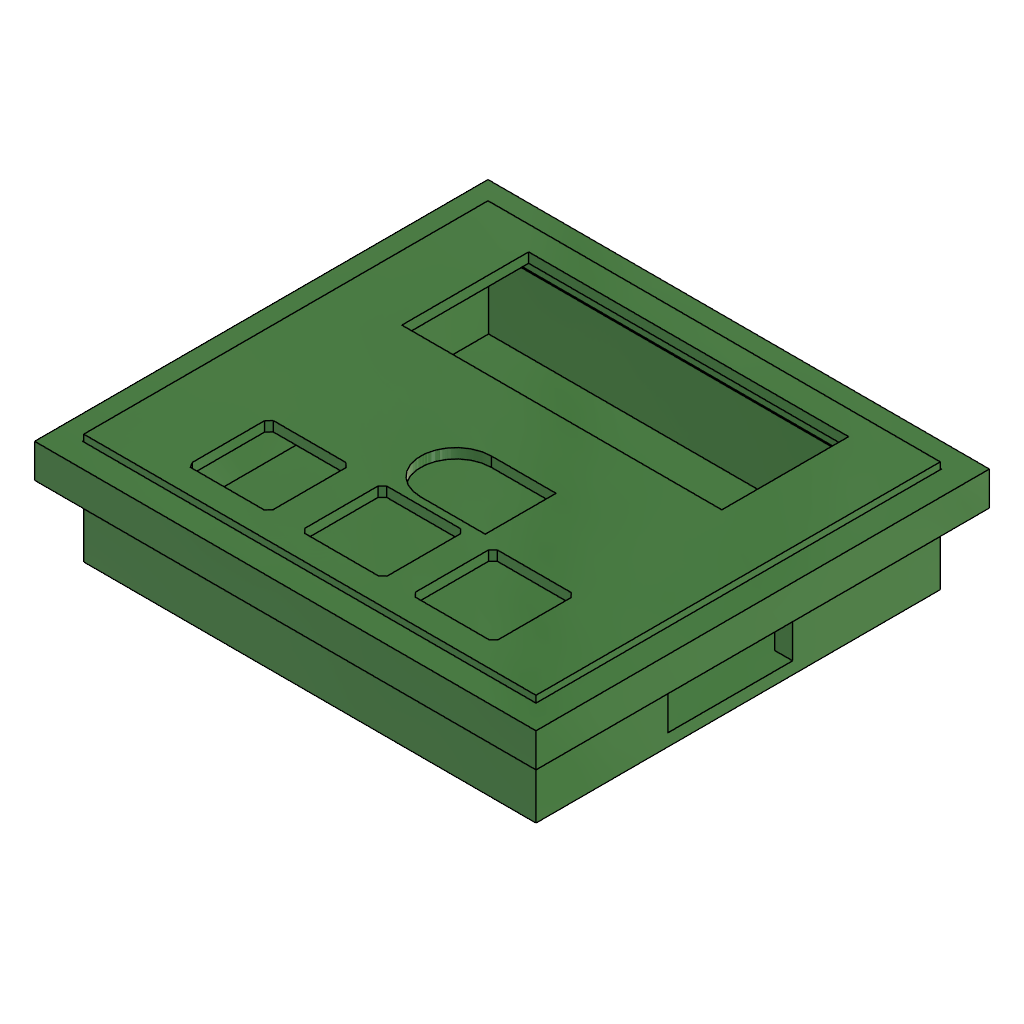
Rhino Motion RMCS-610 digital speed controller (Autodesk Fusion 360 design; units mm, degrees)
part number: 2026-09-15-11-50-59-737
Autodesk Fusion 360 part; units mm, degrees
sketch "Sketch1" plane through (0, 0, 0) normal (0, 0, 1) x (1, 0, 0)
  line L0 (0, 0) -> (67.5, 0)
  line L1 (67.5, 0) -> (67.5, 59.7)
  line L2 (67.5, 59.7) -> (0, 59.7)
  line L3 (0, 59.7) -> (0, 0)
  line L4 (8, 58.3) -> (59, 58.3)
  line L5 (59, 58.3) -> (59, 38.7)
  line L6 (59, 38.7) -> (8, 38.7)
  line L7 (8, 38.7) -> (8, 58.3)
  circle A0 centre (33.2, 21.3) radius 5.75
  line L8 (28.2142, 1.7129) -> (28.2142, 13.6129)
  line L9 (28.2142, 13.6129) -> (28.9271, 14.3142)
  line L10 (40.9271, 14.3142) -> (41.6283, 13.6012)
  line L11 (40.9154, 1) -> (28.9154, 1)
  line L12 (28.9154, 1) -> (28.2142, 1.7129)
  line L13 (41.6283, 1.7012) -> (40.9154, 1)
  line L14 (28.9271, 14.3142) -> (40.9271, 14.3142)
  line L15 (41.6283, 13.6012) -> (41.6283, 1.7012)
  line L16 (46.1883, 1.7129) -> (46.1883, 13.6129)
  line L17 (46.1883, 13.6129) -> (46.9013, 14.3142)
  line L18 (58.9013, 14.3142) -> (59.6025, 13.6012)
  line L19 (58.8895, 1) -> (46.8895, 1)
  line L20 (46.8895, 1) -> (46.1883, 1.7129)
  line L21 (59.6025, 1.7012) -> (58.8895, 1)
  line L22 (46.9013, 14.3142) -> (58.9013, 14.3142)
  line L23 (59.6025, 13.6012) -> (59.6025, 1.7012)
  circle A1 centre (34.453, 7.8982) radius 3.315
  circle A2 centre (52.6325, 7.8982) radius 3.315
  line L24 (22.3245, 1) -> (10.3245, 1)
  line L25 (22.29, 14.3138) -> (23.0142, 13.6241)
  circle A3 centre (16.2543, 7.8982) radius 3.315
  line L26 (9.8, 13.5897) -> (10.4897, 14.3138)
  line L27 (23.0142, 1.7241) -> (22.3245, 1)
  line L28 (10.3245, 1) -> (9.8, 1.8514)
  line L29 (23.0142, 13.6241) -> (23.0142, 1.7241)
  line L30 (9.8, 1.8514) -> (9.8, 13.5897)
  line L31 (10.4897, 14.3138) -> (22.29, 14.3138)
  line L32 (33.2, 27.05) -> (43.7, 27.05)
  line L33 (43.7, 27.05) -> (43.7, 15.55)
  line L34 (33.2, 27.05) -> (33.2, 15.55)
  line L35 (33.2, 15.55) -> (43.7, 15.55)
  dimension "d1" = 59.7
  dimension "d2" = 67.5
  dimension "d11" = 51
  dimension "d12" = 19.6
  dimension "d13" = 1.4
  dimension "d15" = 11.5
  dimension "d29" = 1
  dimension "d30" = 1
  dimension "d31" = 1
  dimension "d32" = 1
  dimension "d34" = 12
  dimension "d36" = 11.9
  dimension "d37" = 1
  dimension "d38" = 1
  dimension "d39" = 1
  dimension "d40" = 1
  dimension "d41" = 12
  dimension "d44" = 11.9
  dimension "d46" = 4.56
  dimension "d50" = 1
  dimension "d51" = 1
  dimension "d61" = 6.63
  dimension "d62" = 6.63
  dimension "d68" = 1
  dimension "d69" = 1
  dimension "d70" = 1
  dimension "d71" = 1
  dimension "d73" = 12
  dimension "d75" = 11.9
  dimension "d76" = 6.63
  dimension "d79" = 5.2
  dimension "d80" = 1
  dimension "d83" = 9.8
  dimension "d84" = 8
  dimension "d336" = 10.5
  dimension "d337" = 11.65
  dimension "d338" = 23.8
  constraint horizontal L0
  constraint vertical L1
  constraint horizontal L2
  constraint vertical L3
  constraint coincident L0.start L3.end
  constraint horizontal L4
  constraint vertical L5
  constraint horizontal L6
  constraint vertical L7
  constraint perpendicular L9 L10
  constraint perpendicular L14 L15
  constraint perpendicular L10 L13
  constraint perpendicular L11 L15
  constraint perpendicular L17 L18
  constraint perpendicular L22 L23
  constraint perpendicular L18 L21
  constraint perpendicular L19 L23
  constraint perpendicular L25 L26
  constraint perpendicular L29 L31
  constraint perpendicular L25 L27
  constraint perpendicular L24 L29
  constraint coincident A0 L32.start
  constraint tangent A0 L32
  constraint horizontal L32
  constraint perpendicular L32 L33
  constraint coincident A0 L34.end
  constraint perpendicular A0 L34
  constraint horizontal L35
  constraint horizontal A1.centre A2.centre
  constraint horizontal A1.centre A3.centre
  measures "d1" distance of L0.end L1.end
  measures "d2" distance of L1.end L2.end
  measures "d11" distance of L5.end L6.end
  measures "d12" distance of L4.end L5.end
  measures "d13" distance of L2 L4
  measures "d15" diameter of A0
  measures "d29" distance of L8.end L9.end
  measures "d30" distance of L10.start L10.end
  measures "d31" distance of L8.start L11.end
  measures "d32" distance of L13.start L11.start
  measures "d34" distance of L11.end L11.start
  measures "d36" distance of L13.start L10.end
  measures "d37" distance of L16.end L17.end
  measures "d38" distance of L18.start L18.end
  measures "d39" distance of L16.start L19.end
  measures "d40" distance of L21.start L19.start
  measures "d41" distance of L17.end L18.start
  measures "d44" distance of L21.start L18.end
  measures "d46" distance of L15 L16
  measures "d50" distance of L0 L11
  measures "d51" distance of L0 L19
  measures "d61" diameter of A1
  measures "d62" diameter of A2
  measures "d68" distance of L26.start L26.end
  measures "d69" distance of L25.end L25.start
  measures "d70" distance of L28.end L24.end
  measures "d71" distance of L27.start L24.start
  measures "d73" distance of L24.end L24.start
  measures "d75" distance of L25.end L27.start
  measures "d76" diameter of A3
  measures "d79" distance of L8 L29
  measures "d80" distance of L0 L24
  measures "d83" distance of L3 L30
  measures "d84" distance of L3 L7
  measures "d336" distance of L32.start L32.end
  measures "d337" distance of L6 L32
  measures "d338" distance of L1 L33
sketch "Sketch2" plane through (0, 0, 0) normal (0, 0, 1) x (1, 0, 0)
  line L0 (55.5, 18.44) -> (63.5, 18.44)
  line L1 (63.5, 18.44) -> (63.5, 38.7)
  line L2 (63.5, 38.7) -> (55.5, 38.7)
  line L3 (55.5, 38.7) -> (55.5, 18.44)
  line L4 (67.5, 59.7) -> (0, 59.7)
  line L5 (67.5, 0) -> (67.5, 59.7)
  dimension "d86" = 20.26
  dimension "d87" = 8
  dimension "d88" = 21
  dimension "d89" = 4
  constraint horizontal L0
  constraint vertical L1
  constraint horizontal L2
  constraint vertical L3
  measures "d86" distance of L0.end L1.end
  measures "d87" distance of L0.start L0.end
  measures "d88" distance of L2 L4
  measures "d89" distance of L1 L5
extrude "Extrude99" add sketch "Sketch1" along normal blind 1.6 contours L0 L1 L2 L3 makes body 1
extrude "Extrude100" add sketch "Sketch2" against normal blind 10.4 bodies 1
extrude "Extrude101" add sketch "Sketch1" along normal blind 1 contours A0 L32 L33 L35 | L8 L9 L10 L11 L12 L13 L14 L15 | L16 L17 L18 L19 L20 L21 L22 L23 | L24 L25 L26 L27 L28 L29 L30 L31 bodies 1
extrude "Extrude102" add sketch "Sketch1" along normal blind 2 contours A0 L34 | A0 L34 | A1 | A2 | A3 bodies 1
extrude "Extrude103" add 1 faces at (35.7318, 22.5192, 2) along direction (0, 0, 1) blind 2 on bodies 1 bodies 1
ref_plane "WorkPlane12" through (33.75, 29.85, 1.6) normal (0, 0, 1) x (1, 0, 0)
sketch "Sketch18" plane through (0, 0, 1.6) normal (0, 0, 1) x (1, 0, 0)
  line L0 (0, 59.7) -> (0, 0)
  line L1 (0, 0) -> (67.5, 0)
  line L2 (67.5, 0) -> (67.5, 59.7)
  line L3 (67.5, 59.7) -> (0, 59.7)
  line L4 (9.8, 1.8514) -> (9.8, 13.5897)
  line L5 (22.3245, 1) -> (10.3245, 1)
  line L6 (10.4897, 14.3138) -> (22.29, 14.3138)
  line L7 (9.8, 13.5897) -> (10.4897, 14.3138)
  line L8 (10.3245, 1) -> (9.8, 1.8514)
  line L9 (23.0142, 1.7241) -> (22.3245, 1)
  line L10 (23.0142, 13.6241) -> (23.0142, 1.7241)
  line L11 (22.29, 14.3138) -> (23.0142, 13.6241)
  line L12 (28.9154, 1) -> (28.2142, 1.7129)
  line L13 (28.2142, 1.7129) -> (28.2142, 13.6129)
  line L14 (28.2142, 13.6129) -> (28.9271, 14.3142)
  line L15 (40.9154, 1) -> (28.9154, 1)
  line L16 (28.9271, 14.3142) -> (40.9271, 14.3142)
  line L17 (40.9271, 14.3142) -> (41.6283, 13.6012)
  line L18 (41.6283, 13.6012) -> (41.6283, 1.7012)
  line L19 (41.6283, 1.7012) -> (40.9154, 1)
  line L20 (46.8895, 1) -> (46.1883, 1.7129)
  line L21 (46.1883, 1.7129) -> (46.1883, 13.6129)
  line L22 (46.1883, 13.6129) -> (46.9013, 14.3142)
  line L23 (46.9013, 14.3142) -> (58.9013, 14.3142)
  line L24 (58.8895, 1) -> (46.8895, 1)
  line L25 (59.6025, 1.7012) -> (58.8895, 1)
  line L26 (59.6025, 13.6012) -> (59.6025, 1.7012)
  line L27 (58.9013, 14.3142) -> (59.6025, 13.6012)
  line L28 (43.7, 15.55) -> (33.2, 15.55)
  line L29 (43.7, 27.05) -> (43.7, 15.55)
  line L30 (33.2, 27.05) -> (43.7, 27.05)
  arc A0 (33.2, 27.05) -> (33.2, 15.55) centre (33.2, 21.3) ccw
  line L31 (59, 38.7) -> (8, 38.7)
  line L32 (8, 38.7) -> (8, 58.3)
  line L33 (8, 58.3) -> (59, 58.3)
  line L34 (59, 58.3) -> (59, 38.7)
  line L35 (-3, -3) -> (70.5, -3)
  line L36 (70.5, -3) -> (70.5, 62.7)
  line L37 (70.5, 62.7) -> (-3, 62.7)
  line L38 (-3, 62.7) -> (-3, -3)
  dimension "d351" = 3
extrude "Extrude104" add sketch "Sketch18" along normal blind 4 separate body contours L0 L1 L2 L3 | L35 L36 L37 L38 makes body 2
extrude "Extrude105" cut 1 faces at (15.4457, 25.4715, 5.6) along direction (0, 0, -1) blind 1 on bodies 2 bodies 2
extrude "Extrude106" cut sketch "Sketch1" along normal blind 4 contours L0 L1 L2 L3 bodies 2
extrude "Extrude107" add 1 faces at (15.4457, 25.4715, 4.6) along direction (0, 0, 1) blind 1 on bodies 2 bodies 2
extrude "Extrude108" cut 1 faces at (67.5, 19.9, 2.4) along direction (1, 0, 0) blind 0.5 on bodies 2 bodies 2
extrude "Extrude109" cut 1 faces at (22.6667, 0, 2.4) along direction (0, -1, 0) blind 0.5 on bodies 2 bodies 2
extrude "Extrude110" cut 1 faces at (45.3333, 59.7, 3.2) along direction (0, 1, 0) blind 0.5 on bodies 2 bodies 2
extrude "Extrude111" cut 1 faces at (0, 19.7333, 3.2) along direction (-1, 0, 0) blind 0.5 on bodies 2 bodies 2
ref_plane "WorkPlane13" through (59.5, 28.57, -11.4) normal (0, 0, -1) x (-1, 0, 0)
sketch "Sketch20" plane through (0, 0, -11.4) normal (0, 0, -1) x (-1, 0, 0)
  line L0 (0, 59.7) -> (0, 0)
  line L1 (0, 0) -> (-67.5, 0)
  line L2 (-67.5, 0) -> (-67.5, 59.7)
  line L3 (-67.5, 59.7) -> (0, 59.7)
  line L4 (-70.5, 62.7) -> (3, 62.7)
  line L5 (-70.5, -3) -> (-70.5, 62.7)
  line L6 (3, -3) -> (-70.5, -3)
  line L7 (3, 62.7) -> (3, -3)
  line L8 (-67.5, 0) -> (-67.5, 59.7)
  line L9 (1.7012, 61.4012) -> (1.7012, -1.7012)
  line L10 (1.7012, -1.7012) -> (-69.2012, -1.7012)
  line L11 (-69.2012, -1.7012) -> (-69.2012, 61.4012)
  line L12 (-69.2012, 61.4012) -> (1.7012, 61.4012)
  line L13 (1.581, -1.581) -> (-69.081, -1.581)
  line L14 (-69.081, -1.581) -> (-69.081, 61.281)
  line L15 (-69.081, 61.281) -> (1.581, 61.281)
  line L16 (1.581, 61.281) -> (1.581, -1.581)
  dimension "d382" = 0
  dimension "d383" = -1.7012
  dimension "d384" = 0.1201
  measures "d382" distance of L2
extrude "Extrude112" add sketch "Sketch20" against normal blind 13 separate body contours L0 L1 L2 L3 L8 | L4 L5 L6 L7 | L9 L10 L11 L12 | L13 L14 L15 L16 makes body 3
ref_plane "WorkPlane14" through (33.75, 29.85, 1.6) normal (0, 0, 1) x (1, 0, 0)
sketch "Sketch21" plane through (0, 0, 1.6) normal (0, 0, 1) x (1, 0, 0)
  line L0 (70.5, -3) -> (70.5, 62.7)
  line L1 (67.5, 0) -> (67.5, 59.7)
  line L2 (67.5, 59.7) -> (0, 59.7)
  line L3 (70.5, 62.7) -> (-3, 62.7)
  line L4 (-3, 62.7) -> (-3, -3)
  line L5 (0, 59.7) -> (0, 0)
  line L6 (-3, -3) -> (70.5, -3)
  line L7 (0, 0) -> (67.5, 0)
extrude "Extrude113" cut sketch "Sketch21" against normal blind 11 contours L1 L2 L5 L7 bodies 3
ref_plane "WorkPlane15" through (70.5, 29.85, -4.9) normal (1, 0, 0) x (0, 1, 0)
sketch "Sketch22" plane through (70.5, 0, 0) normal (1, 0, 0) x (0, 1, 0)
  line L0 (18.44, 0) -> (18.44, -10.4)
  line L1 (38.7, -10.4) -> (18.44, -10.4)
  line L2 (38.7, 0) -> (38.7, -10.4)
  line L3 (18.44, 0) -> (38.7, 0)
extrude "Extrude114" cut sketch "Sketch22" against normal blind 3 bodies 3
extrude "Extrude115" cut 1 faces at (22.5, 32.8, -9.4) along direction (0, 0, -1) blind 1 on bodies 3 bodies 1 3
extrude "Extrude116" cut 1 faces at (25, 58.3, 5.0667) along direction (0, 1, 0) blind 0.5 on bodies 2 bodies 2
extrude "Extrude117" cut 1 faces at (8, 45.4, 4.5333) along direction (-1, 0, 0) blind 0.5 on bodies 2 bodies 2
extrude "Extrude118" cut 1 faces at (59, 52.1, 5.0667) along direction (1, 0, 0) blind 0.5 on bodies 2 bodies 2
extrude "Extrude119" cut 1 faces at (24.8333, 38.7, 4.5333) along direction (0, -1, 0) blind 0.5 on bodies 2 bodies 2
ref_plane "WorkPlane16" through (33.75, 29.85, 1.6) normal (0, 0, 1) x (1, 0, 0)
sketch "Sketch23" plane through (0, 0, 1.6) normal (0, 0, 1) x (1, 0, 0)
  line L0 (-3, -3) -> (70.5, -3)
  line L1 (-3, 62.7) -> (-3, -3)
  line L2 (70.5, -3) -> (70.5, 62.7)
  line L3 (70.5, 62.7) -> (-3, 62.7)
  line L4 (-7, 66.7) -> (-7, -7)
  line L5 (-7, -7) -> (74.5, -7)
  line L6 (74.5, -7) -> (74.5, 66.7)
  line L7 (74.5, 66.7) -> (-7, 66.7)
  dimension "d395" = 4
extrude "Extrude120" add sketch "Sketch23" along normal blind 3 separate body makes body 4
extrude "Extrude121" add 1 faces at (46, -5.6667, 1.6) along direction (0, 0, -1) blind 2 separate body on bodies 4 makes body 5
combine "Combine10" operation add target body 3 tool bodies 4 5
extrude "Extrude126" add 1 faces at (21.5, 40.8, -11.4) along direction (0, 0, -1) blind 1 on bodies 3 bodies 3
extrude "Extrude127" add 1 faces at (73.1667, 32.8, -0.4) along direction (0, 0, -1) blind 0.5 on bodies 3 bodies 3
extrude "Extrude128" cut 1 faces at (-3, 40.8, 2.6) along direction (-1, 0, 0) blind 0.1 on bodies 3 bodies 3
extrude "Extrude129" cut 1 faces at (45.9667, 62.7, 3.6) along direction (0, 1, 0) blind 0.1 on bodies 3 bodies 3
extrude "Extrude130" cut 1 faces at (21.4333, -3, 2.6) along direction (0, -1, 0) blind 0.1 on bodies 3 bodies 3
extrude "Extrude131" cut 1 faces at (70.5, 40.8333, 2.6) along direction (1, 0, 0) blind 0.1 on bodies 3 bodies 3
extrude "Extrude132" cut 1 faces at (45, 59.7, -2.4) along direction (0, 1, 0) blind 0.3 on bodies 3 bodies 3
extrude "Extrude133" cut 1 faces at (22.5, 0, -2.4) along direction (0, -1, 0) blind 0.2 on bodies 3 bodies 3
extrude "Extrude134" cut 1 faces at (0, 39.9333, -2.4) along direction (-1, 0, 0) blind 0.2 on bodies 3 bodies 3
extrude "Extrude135" cut 1 faces at (67.5, 52.9, -2.9333) along direction (1, 0, 0) blind 0.1 on bodies 3 bodies 3
hidden bodies 1
named bodies: "component", "top", "bottom"
